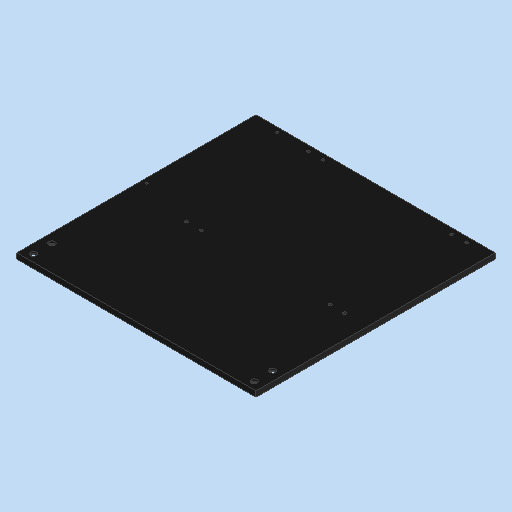
# Autodesk Inventor part: MM0937AN106_G25_200
Saved by Autodesk Inventor 2023.3 (Build 273359000, 359)
## iProperties
Created: 2023-11-09
Part Number: MM0937AN106_G25_200
Material: Kst - Pa 66 GF30  (schwarz)
Description: =<RBPARTNOTITLE2>
Document SubType Name: Modeling
Designer: FSM9BW
Mass: 544.618 g
Surface Area: 1419.84 cm^2
Volume: 403.421 cm^3
Density: 1.35 g/cm^3
Appearance: schwarz AnP
RBPARTMADEOF: 6 x 240 x 260 (FM)
RBDRAWINGMISSINGSPEC: --
AnP_Kategorie: 1
RBPARTNOTITLE2: Anfertigungsteil
RBSURFACE: --
RBPARTNOTITLE1: manufactured part
RBSURFACE2: --
AnP_Material: =<Material>
RBMATERIAL: =<Material>
RBMATNO: =<Part Number>
RBPARTNO: SIEHE MNR
MaxAbmaße: 6 x 240 x 260 (FM)
Author: FSM9BW
Keywords: =<RBPARTMADEOF>
Comments: =<RBSURFACE2>
Revision Number: 01
Autodesk Inventor part; units mm, degrees
ref_plane "YZ Plane" through (0, 0, 0) normal (1, 0, 0) x (0, 1, 0)
ref_plane "XZ Plane" through (0, 0, 0) normal (0, 1, 0) x (-1, 0, 0)
ref_plane "XY Plane" through (0, 0, 0) normal (0, 0, 1) x (1, 0, 0)
sketch "Skizze1" plane through (0, 0, 0) normal (0, 0, 1) x (1, 0, 0)
  line L0 (-130, 0) -> (130, 0)
  line L1 (130, 0) -> (130, 260)
  line L2 (130, 260) -> (-130, 260)
  line L3 (-130, 260) -> (-130, 0)
  line L4 (-182, 0) -> (182, 0) projected
  line L5 (0, -52) -> (0, 312) projected
  point P0 (0, 0)
  dimension "d0" = 260
  dimension "d1" = 260
  constraints: 8 end point, 2 parallel, 1 collinear, 1 horizontal, 1 perpendicular, 1 other
  measures "d0" distance of L0.start L0.end
  measures "d1" distance of L2.end L0.start
extrude "Extrusion1" add sketch "Skizze1" along normal blind 6
sketch "Skizze2" plane through (0, 0, 6) normal (0, 0, 1) x (1, 0, 0)
  line L0 (130, 260) -> (-130, 260) projected
  line L1 (130, 0) -> (130, 260) projected
  point P0 (0, 0)
  point P1 (89, 254)
  point P2 (-51, 254)
  point P3 (-67, 121.5)
  point P4 (105, 121.5)
  point P5 (105, 254)
  point P6 (-67, 254)
  point P7 (89, 121.5)
  point P8 (-51, 121.5)
  dimension "d4" = 140
  dimension "d5" = 6
  dimension "d6" = 41
  dimension "d7" = 172
  dimension "d8" = 16
  dimension "d9" = 132.5
  constraints: 6 horizontal alignment, 4 vertical alignment
  measures "d4" distance of point (89, 254) point (-51, 254)
  measures "d5" distance from line of point (89, 254) L0
  measures "d6" distance from line of L1 point (89, 254)
  measures "d7" distance of point (105, 121.5) point (-67, 121.5)
  measures "d8" horizontal distance of point (89, 254) point (105, 121.5)
  measures "d9" vertical distance of point (89, 254) point (105, 121.5)
hole "Bohrung1" at (89, 254, 6) at (-51, 254, 6) at (-67, 121.5, 6) at (105, 121.5, 6) at (105, 254, 6) at (-67, 254, 6) at (-51, 121.5, 6) at (89, 121.5, 6) direction (0, 0, -1) diameter 3.242 end through all thread size "M4x0.7" designation "M4" class "6H" standard "ISO Metric profile"
sketch "Skizze3" plane through (0, 0, 0) normal (0, 0, 1) x (1, 0, 0)
  line L0 (-130, 0) -> (130, 0) projected
  point P0 (0, 0)
  point P1 (-120, 8)
  point P2 (-120, 28)
  point P3 (120, 8)
  point P4 (120, 28)
  point P5 (0, 0)
  dimension "d17" = 8
  dimension "d18" = 20
  dimension "d19" = 240
  dimension "d20" = 120
  constraints: 2 horizontal alignment, 2 vertical alignment, 1 midpoint
  measures "d17" distance from line of point (-120, 8) L0
  measures "d18" distance of point (-120, 28) point (-120, 8)
  measures "d19" distance of point (120, 8) point (-120, 8)
  measures "d20" horizontal distance of point (-120, 8) point (0, 0)
sketch "Skizze4" plane through (0, 0, 6) normal (0, 0, 1) x (1, 0, 0)
  line L0 (-130, 260) -> (-130, 0) projected
  line L1 (130, 260) -> (-130, 260) projected
  point P0 (0, 0)
  point P1 (-102, 255)
  point P2 (-125, 136)
  dimension "d28" = 5
  dimension "d29" = 119
  dimension "d30" = 5
  dimension "d31" = 23
  measures "d28" distance from line of point (-125, 136) L0
  measures "d29" vertical distance of point (-102, 255) point (-125, 136)
  measures "d30" distance from line of point (-102, 255) L1
  measures "d31" horizontal distance of point (-102, 255) point (-125, 136)
hole "Bohrung3" at (-102, 255, 6) at (-125, 136, 6) direction (0, 0, -1) diameter 2.459 end through all thread size "M3x0.5" designation "M3" class "6H" standard "ISO Metric profile"
hole "Bohrung4" at (-120, 8, 0) at (-120, 28, 0) at (120, 8, 0) at (120, 28, 0) direction (0, 0, 1) diameter 6.6 end through all countersink diameter 14.5 countersink angle 90 clearance for "Innensechskant-Senkkopfschraube ISO 10642" size "M6" standard "ISO"
